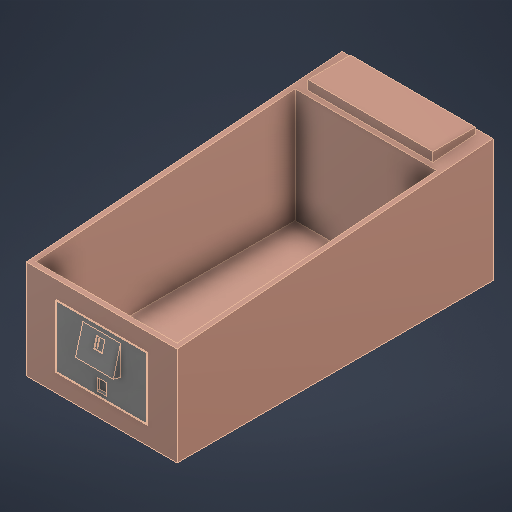
# Autodesk Inventor part: Box
Saved by Autodesk Inventor 2027 (Build 310192060, 192F)
## iProperties
Created: 2026-10-17
Part Number: Box
Material: Générique
Document SubType Name: Modeling
Designer: strei
Density: 1 g/cm^3
Appearance: Lisse - Brun foncé
Author: strei
Autodesk Inventor part; units mm, degrees
ref_plane "YZ Plane" through (0, 0, 0) normal (1, 0, 0) x (0, 1, 0)
ref_plane "XZ Plane" through (0, 0, 0) normal (0, 1, 0) x (-1, 0, 0)
ref_plane "XY Plane" through (0, 0, 0) normal (0, 0, 1) x (1, 0, 0)
sketch "Esquisse1" plane through (0, 0, 0) normal (1, 0, 0) x (0, 1, 0)
  line L0 (0, 650) -> (0, -650)
  line L1 (0, -650) -> (500, -650)
  line L2 (500, -650) -> (400, 650)
  line L3 (400, 650) -> (0, 650)
  point P0 (0, 0)
  point P1 (0, 0)
  dimension "d0" = 1300
  dimension "d1" = 500
  dimension "d2" = 400
  dimension "d6" = 94.399
  constraints: 8 end point, 2 perpendicular, 1 coincident, 1 midpoint, 1 vertical
  measures "d0" distance of L0.start L0.end
  measures "d1" distance of L0.end L1.end
  measures "d2" distance of L0.start L2.end
  measures "d6" angle of L2 L3
extrude "Extrusion1" add sketch "Esquisse1" along normal mid plane 600
shell "Coque1" thickness 20 outward yes removed faces 1 at (100, 433.3333, 216.6667)
move faces "Déplacer1" translate (0, 0, 200) faces at (100, 333.3333, -650)
sketch "Esquisse2" plane through (0, 0, 0) normal (1, 0, 0) x (0, 1, 0)
  line L0 (398.4615, 670) -> (501.5385, -670) projected
  line L1 (486.1538, -470) -> (526.1538, -470)
  line L2 (526.1538, -470) -> (526.1538, -650)
  line L3 (526.1538, -650) -> (500, -650)
  line L4 (486.1538, -470) -> (500, -650)
  line L5 (501.5385, -670) -> (-20, -670) projected
  line L6 (484.6154, -450) -> (0, -450) projected
  point P0 (0, 0)
  point P1 (526.1538, -560)
  dimension "d10" = 180
  dimension "d11" = 40
  dimension "d12" = 220
  dimension "d13" = 110
  constraints: 8 end point, 2 perpendicular, 2 point on line, 1 collinear, 1 horizontal, 1 midpoint
  measures "d10" distance of L1.end L2.end
  measures "d11" distance of L1.start L1.end
  measures "d12" distance between parallel lines of L5 L6
  measures "d13" distance from line of point (526.154, -560) L6
extrude "Extrusion2" add sketch "Esquisse2" along normal mid plane 530
sketch "Esquisse3" plane through (-320, -20, 670) normal (0, 0, 1) x (1, 0, 0)
  line L0 (130, 339.2308) -> (510, 339.2308)
  line L1 (510, 339.2308) -> (510, 79.2308)
  line L2 (510, 79.2308) -> (130, 79.2308)
  line L3 (130, 79.2308) -> (130, 339.2308)
  line L4 (130, 339.2308) -> (510, 79.2308) construction
  line L5 (510, 339.2308) -> (130, 79.2308) construction
  line L6 (640, 418.4615) -> (640, 0) projected
  line L7 (514, 343.2308) -> (126, 343.2308)
  line L8 (126, 343.2308) -> (126, 75.2308)
  line L9 (126, 75.2308) -> (514, 75.2308)
  line L10 (514, 75.2308) -> (514, 343.2308)
  point P0 (320, 20)
  point P1 (320, 209.2308)
  point P2 (640, 209.2308)
  dimension "d16" = 380
  dimension "d17" = 260
  dimension "d18" = 4
  constraints: 20 end point, 4 parallel, 3 midpoint, 2 perpendicular, 1 horizontal, 1 horizontal alignment, 1 vertical alignment, 3 other
  measures "d16" distance of L0.start L0.end
  measures "d17" distance of L0.end L1.end
  measures "d18" distance between parallel lines of L0 L7
extrude "Extrusion3" cut sketch "Esquisse3" against normal blind 2
sketch "Esquisse4" plane through (0, 0, 0) normal (1, 0, 0) x (0, 1, 0)
  line L0 (319.2308, 670) -> (59.2308, 670) projected
  line L1 (299.2308, 670) -> (183.3197, 701.0583)
  line L2 (183.3197, 701.0583) -> (174.9976, 670)
  line L3 (174.9976, 670) -> (299.2308, 670)
  line L4 (55.2308, 668) -> (323.2308, 668) projected
  point P0 (0, 0)
  dimension "d21" = 15
  dimension "d22" = 120
  dimension "d23" = 20
  constraints: 6 end point, 1 parallel, 1 perpendicular, 1 point on line
  measures "d21" angle of L0 L1
  measures "d22" distance of L1.start L1.end
  measures "d23" distance of L0.start L1.start
extrude "Extrusion4" add sketch "Esquisse4" along normal mid plane 160
sketch "Esquisse5" plane through (-80, 183.3197, 701.0583) normal (0, 0.258819, 0.9659258) x (1, 0, 0)
  line L0 (62.5, 102.5) -> (97.5, 102.5)
  line L1 (97.5, 102.5) -> (97.5, 57.5)
  line L2 (97.5, 57.5) -> (62.5, 57.5)
  line L3 (62.5, 57.5) -> (62.5, 102.5)
  line L4 (62.5, 102.5) -> (97.5, 57.5) construction
  line L5 (97.5, 102.5) -> (62.5, 57.5) construction
  line L6 (0, 120) -> (160, 120) projected
  point P0 (80, 4.374)
  point P1 (80, 80)
  dimension "d26" = 40
  dimension "d27" = 35
  dimension "d28" = 45
  constraints: 12 end point, 2 midpoint, 2 parallel, 1 horizontal, 1 perpendicular, 1 vertical alignment
  measures "d26" distance from line of L6 point (80, 80)
  measures "d27" distance of L0.start L0.end
  measures "d28" distance of L2.end L0.start
extrude "Extrusion5" cut sketch "Esquisse5" against normal blind 4
sketch "Esquisse6" plane through (-80, 182.2844, 697.1946) normal (0, 0.258819, 0.9659258) x (1, 0, 0)
  line L0 (71, 97.5) -> (74, 97.5)
  line L1 (74, 97.5) -> (74, 62.5)
  line L2 (74, 62.5) -> (71, 62.5)
  line L3 (71, 62.5) -> (71, 97.5)
  line L4 (71, 97.5) -> (74, 62.5) construction
  line L5 (74, 97.5) -> (71, 62.5) construction
  line L6 (62.5, 57.5) -> (62.5, 102.5) projected
  point P0 (80, 4.374)
  point P1 (72.5, 80)
  point P2 (62.5, 80)
  dimension "d31" = 10
  dimension "d32" = 35
  dimension "d33" = 3
  constraints: 12 end point, 3 midpoint, 2 parallel, 1 horizontal, 1 horizontal alignment, 1 perpendicular
  measures "d31" distance from line of L6 point (72.5, 80)
  measures "d32" distance of L0.end L1.end
  measures "d33" distance of L0.start L0.end
extrude "Extrusion6" cut sketch "Esquisse6" against normal blind 15
sketch "Esquisse7" plane through (-190, 319.2308, 670) normal (0, 0, 1) x (1, 0, 0)
  line L0 (170, -194.2308) -> (210, -194.2308)
  line L1 (210, -194.2308) -> (210, -244.2308)
  line L2 (210, -244.2308) -> (170, -244.2308)
  line L3 (170, -244.2308) -> (170, -194.2308)
  line L4 (170, -194.2308) -> (210, -244.2308) construction
  line L5 (210, -194.2308) -> (170, -244.2308) construction
  point P0 (190, -319.2308)
  point P1 (190, -219.2308)
  dimension "d36" = 50
  dimension "d37" = 40
  dimension "d38" = 100
  constraints: 12 end point, 2 midpoint, 2 parallel, 1 horizontal, 1 perpendicular, 1 vertical alignment
  measures "d36" distance of L2.end L0.start
  measures "d37" distance of L0.start L0.end
  measures "d38" distance of point (190, -219.231) point (190, -319.231)
extrude "Extrusion7" cut sketch "Esquisse7" against normal blind 12
equation "\"d13\" = 0.5 * d12"
